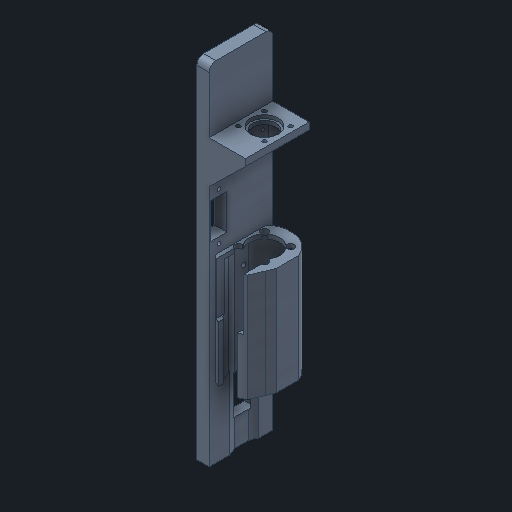
# Autodesk Inventor part: OT2-Pipette V0.3 - frame
Saved by Autodesk Inventor 2026 (Build 300175000, 175)
## iProperties
Created: 2026-11-01
Part Number: OT2-Pipette V0.3 - frame
Material: Generisch
Description: printed frame: mount wall with 3 M3 inserts, sleeve + ledge, header window, motor shelf (PETG/ASA)
Document SubType Name: Modeling
Designer: benir
Density: 1 g/cm^3
Appearance: Light Steel Blue
Author: benir
Autodesk Inventor part; units mm, degrees
ref_plane "WP mount face" through (-9.5, 0, 0) normal (1, 0, 0) x (0, 1, 0)
ref_plane "WP pipette x" through (8.2, 0, 0) normal (1, 0, 0) x (0, 1, 0)
ref_plane "WP pipette z" through (0, 0, -3.46) normal (0, 0, 1) x (1, 0, 0)
ref_plane "WP motor seat" through (0, 119, 0) normal (0, 1, 0) x (-1, 0, 0)
ref_plane "y=ins_top_y" through (0, 46, 0) normal (0, 1, 0) x (-1, 0, 0)
ref_plane "z=ins_z" through (0, 0, 13.25) normal (0, 0, 1) x (1, 0, 0)
ref_plane "z=-ins_z" through (0, 0, -13.25) normal (0, 0, 1) x (1, 0, 0)
ref_plane "y=ins_bot_y" through (0, -43, 0) normal (0, 1, 0) x (-1, 0, 0)
sketch "mount wall" plane through (-9.5, 0, 0) normal (1, 0, 0) x (0, 1, 0)
  line L0 (-49, -18.75) -> (156.35, -18.75)
  line L1 (156.35, -18.75) -> (156.35, 18.75)
  line L2 (156.35, 18.75) -> (-49, 18.75)
  line L3 (-49, 18.75) -> (-49, -18.75)
  line L4 (0, -26.25) -> (0, 26.25) projected
  line L5 (-90.07, 0) -> (197.42, 0) projected
  point P0 (0, 0)
  dimension "d10" = 205.35
  dimension "d11" = 37.5
  dimension "d12" = 49
  dimension "d13" = 18.75
  constraints: 8 end point, 2 parallel, 1 horizontal, 1 perpendicular
  measures "d10" distance of L0.start L0.end
  measures "d11" distance of L2.end L0.start
  measures "d12" horizontal distance of point (0, 0) L2.end
  measures "d13" vertical distance of point (0, 0) L0.start
extrude "Extrusion2" add sketch "mount wall" along normal blind 7.3
fillet "wall top edges" radius 4 2 edges at (-5.85, 156.35, 18.75) (-5.85, 156.35, -18.75)
ref_plane "y=sleeve_y0" through (0, -6, 0) normal (0, 1, 0) x (-1, 0, 0)
sketch "sleeve outline" plane through (0, -6, 0) normal (0, 1, 0) x (-1, 0, 0)
  arc A0 (-20.2, -6.2935) -> (3.8, -6.2935) centre (-8.2, -3.46) ccw construction
  arc A1 (-1.2, 13.79) -> (-15.2, 13.79) centre (-8.2, 2.54) ccw construction
  line L0 (3.8, -6.2935) -> (3.8, 1.71) construction
  line L1 (3.8, 1.71) -> (1.58, 7.29) construction
  line L2 (1.58, 7.29) -> (-1.2, 13.79) construction
  line L3 (-15.2, 13.79) -> (-17.98, 7.29) construction
  line L4 (-17.98, 7.29) -> (-20.2, 1.71) construction
  line L5 (-20.2, 1.71) -> (-20.2, -6.2935) construction
  arc A2 (-23.5, -6.6548) -> (7.1, -6.6548) centre (-8.2, -3.46) ccw
  line L6 (7.1, -6.6548) -> (7.1, 2.3423)
  line L7 (7.1, 2.3423) -> (4.6307, 8.549)
  line L8 (4.6307, 8.549) -> (1.4503, 15.9853)
  arc A3 (1.4503, 15.9853) -> (-17.8503, 15.9853) centre (-8.2, 2.54) ccw
  line L9 (-17.8503, 15.9853) -> (-21.0307, 8.549)
  line L10 (-21.0307, 8.549) -> (-23.5, 2.3423)
  line L11 (-23.5, 2.3423) -> (-23.5, -6.6548)
  point P0 (0, 0)
  dimension "lever_drop" = 1.5
  dimension "d18" = 3.46
  dimension "d19" = 8.2
  dimension "d20" = 2.54
  dimension "d21" = 8.2
  dimension "d22" = 6.2935
  dimension "d23" = 20.2
  dimension "d24" = 3.8
  dimension "d25" = 13.79
  dimension "d26" = 15.2
  dimension "d27" = 1.2
  dimension "d28" = 1.71
  dimension "d29" = 3.8
  dimension "d30" = 7.29
  dimension "d31" = 1.58
  dimension "d32" = 7.29
  dimension "d33" = 17.98
  dimension "d34" = 1.71
  dimension "d35" = 20.2
  dimension "d36" = 3.3
  constraints: 24 end point, 8 point on circle, 4 centre point, 7 other
  measures "d18" vertical distance of point (0, 0) A0.centre
  measures "d19" horizontal distance of point (0, 0) A0.centre
  measures "d20" vertical distance of point (0, 0) A1.centre
  measures "d21" horizontal distance of point (0, 0) A1.centre
  measures "d22" vertical distance of point (0, 0) L5.end
  measures "d23" horizontal distance of point (0, 0) L5.end
  measures "d24" horizontal distance of point (0, 0) L0.start
  measures "d25" vertical distance of point (0, 0) L3.start
  measures "d26" horizontal distance of point (0, 0) L3.start
  measures "d27" horizontal distance of point (0, 0) L2.end
  measures "d28" vertical distance of point (0, 0) L0.end
  measures "d29" horizontal distance of point (0, 0) L0.end
  measures "d30" vertical distance of point (0, 0) L1.end
  measures "d31" horizontal distance of point (0, 0) L1.end
  measures "d32" vertical distance of point (0, 0) L3.end
  measures "d33" horizontal distance of point (0, 0) L3.end
  measures "d34" vertical distance of point (0, 0) L4.end
  measures "d35" horizontal distance of point (0, 0) L4.end
  measures "d36" distance between parallel lines of L6 L0
extrude "sleeve and ledge" add sketch "sleeve outline" along normal blind 63.5
ref_plane "y=mot_front - shelf_t" through (0, 115, 0) normal (0, 1, 0) x (-1, 0, 0)
sketch "motor shelf" plane through (0, 115, 0) normal (0, 1, 0) x (-1, 0, 0)
  line L0 (2.7, -18.75) -> (-19.2, -18.75)
  line L1 (-19.2, -18.75) -> (-19.2, 18.75)
  line L2 (-19.2, 18.75) -> (2.7, 18.75)
  line L3 (2.7, 18.75) -> (2.7, -18.75)
  line L4 (0, -26.726) -> (0, 26.726) projected
  line L5 (16.1, 0) -> (-30.1, 0) projected
  point P0 (0, 0)
  dimension "d40" = 21.9
  dimension "d41" = 37.5
  dimension "d42" = 2.7
  dimension "d43" = 18.75
  constraints: 8 end point, 2 parallel, 1 horizontal, 1 perpendicular
  measures "d40" distance of L0.start L0.end
  measures "d41" distance of L2.end L0.start
  measures "d42" horizontal distance of point (0, 0) L2.end
  measures "d43" vertical distance of point (0, 0) L0.start
extrude "Extrusion4" add sketch "motor shelf" along normal blind 4
ref_plane "z=-env_z" through (0, 0, -18.75) normal (0, 0, 1) x (1, 0, 0)
sketch "gusset -z" plane through (0, 0, -18.75) normal (0, 0, 1) x (1, 0, 0)
  line L0 (-2.7, 115) -> (19.2, 115)
  line L1 (19.2, 115) -> (-2.7, 93.6)
  line L2 (-2.7, 93.6) -> (-2.7, 115)
  point P0 (0, 0)
  dimension "d47" = 115
  dimension "d48" = 2.7
  dimension "d49" = 115
  dimension "d50" = 19.2
  dimension "d51" = 93.6
  dimension "d52" = 2.7
  constraints: 6 end point
  measures "d47" vertical distance of point (0, 0) L0.start
  measures "d48" horizontal distance of point (0, 0) L0.start
  measures "d49" vertical distance of point (0, 0) L0.end
  measures "d50" horizontal distance of point (0, 0) L0.end
  measures "d51" vertical distance of point (0, 0) L1.end
  measures "d52" horizontal distance of point (0, 0) L1.end
extrude "Extrusion5" add sketch "gusset -z" along normal blind 2.5
ref_plane "z=env_z - gusset_t" through (0, 0, 16.25) normal (0, 0, 1) x (1, 0, 0)
sketch "gusset +z" plane through (0, 0, 16.25) normal (0, 0, 1) x (1, 0, 0)
  line L0 (-2.7, 115) -> (19.2, 115)
  line L1 (19.2, 115) -> (-2.7, 93.6)
  line L2 (-2.7, 93.6) -> (-2.7, 115)
  point P0 (0, 0)
  dimension "d56" = 115
  dimension "d57" = 2.7
  dimension "d58" = 115
  dimension "d59" = 19.2
  dimension "d60" = 93.6
  dimension "d61" = 2.7
  constraints: 6 end point
  measures "d56" vertical distance of point (0, 0) L0.start
  measures "d57" horizontal distance of point (0, 0) L0.start
  measures "d58" vertical distance of point (0, 0) L0.end
  measures "d59" horizontal distance of point (0, 0) L0.end
  measures "d60" vertical distance of point (0, 0) L1.end
  measures "d61" horizontal distance of point (0, 0) L1.end
extrude "Extrusion6" add sketch "gusset +z" along normal blind 2.5
ref_plane "y=body_bottom - body_cut_below" through (0, -96, 0) normal (0, 1, 0) x (-1, 0, 0)
sketch "body clearance outline" plane through (0, -96, 0) normal (0, 1, 0) x (-1, 0, 0)
  arc A0 (-20.2, -6.2935) -> (3.8, -6.2935) centre (-8.2, -3.46) ccw construction
  arc A1 (-1.2, 13.79) -> (-15.2, 13.79) centre (-8.2, 2.54) ccw construction
  line L0 (3.8, -6.2935) -> (3.8, 1.71) construction
  line L1 (3.8, 1.71) -> (1.58, 7.29) construction
  line L2 (1.58, 7.29) -> (-1.2, 13.79) construction
  line L3 (-15.2, 13.79) -> (-17.98, 7.29) construction
  line L4 (-17.98, 7.29) -> (-20.2, 1.71) construction
  line L5 (-20.2, 1.71) -> (-20.2, -6.2935) construction
  arc A2 (-20.5, -6.3283) -> (4.1, -6.3283) centre (-8.2, -3.46) ccw
  line L6 (4.1, -6.3283) -> (4.1, 1.7675)
  line L7 (4.1, 1.7675) -> (1.8573, 7.4045)
  line L8 (1.8573, 7.4045) -> (-0.9611, 13.9943)
  arc A3 (-0.9611, 13.9943) -> (-15.4389, 13.9943) centre (-8.2, 2.54) ccw
  line L9 (-15.4389, 13.9943) -> (-18.2573, 7.4045)
  line L10 (-18.2573, 7.4045) -> (-20.5, 1.7675)
  line L11 (-20.5, 1.7675) -> (-20.5, -6.3283)
  point P0 (0, 0)
  dimension "d65" = 3.46
  dimension "d66" = 8.2
  dimension "d67" = 2.54
  dimension "d68" = 8.2
  dimension "d69" = 6.2935
  dimension "d70" = 20.2
  dimension "d71" = 3.8
  dimension "d72" = 13.79
  dimension "d73" = 15.2
  dimension "d74" = 1.2
  dimension "d75" = 1.71
  dimension "d76" = 3.8
  dimension "d77" = 7.29
  dimension "d78" = 1.58
  dimension "d79" = 7.29
  dimension "d80" = 17.98
  dimension "d81" = 1.71
  dimension "d82" = 20.2
  dimension "d83" = 0.3
  constraints: 24 end point, 8 point on circle, 4 centre point, 7 other
  measures "d65" vertical distance of point (0, 0) A0.centre
  measures "d66" horizontal distance of point (0, 0) A0.centre
  measures "d67" vertical distance of point (0, 0) A1.centre
  measures "d68" horizontal distance of point (0, 0) A1.centre
  measures "d69" vertical distance of point (0, 0) L5.end
  measures "d70" horizontal distance of point (0, 0) L5.end
  measures "d71" horizontal distance of point (0, 0) L0.start
  measures "d72" vertical distance of point (0, 0) L3.start
  measures "d73" horizontal distance of point (0, 0) L3.start
  measures "d74" horizontal distance of point (0, 0) L2.end
  measures "d75" vertical distance of point (0, 0) L0.end
  measures "d76" horizontal distance of point (0, 0) L0.end
  measures "d77" vertical distance of point (0, 0) L1.end
  measures "d78" horizontal distance of point (0, 0) L1.end
  measures "d79" vertical distance of point (0, 0) L3.end
  measures "d80" horizontal distance of point (0, 0) L3.end
  measures "d81" vertical distance of point (0, 0) L4.end
  measures "d82" horizontal distance of point (0, 0) L4.end
  measures "d83" distance between parallel lines of L6 L0
extrude "body clearance" cut sketch "body clearance outline" along normal blind 151
ref_plane "y=body_top - cut_over" through (0, 54, 0) normal (0, 1, 0) x (-1, 0, 0)
sketch "knob hole" plane through (0, 54, 0) normal (0, 1, 0) x (-1, 0, 0)
  circle A0 centre (-8.2, -3.46) radius 9.1
  point P0 (0, 0)
  dimension "d87" = 3.46
  dimension "d88" = 8.2
  dimension "d89" = 18.2
  constraints: 1 centre point
  measures "d87" vertical distance of point (0, 0) A0.centre
  measures "d88" horizontal distance of point (0, 0) A0.centre
  measures "d89" diameter of A0
extrude "Extrusion8" cut sketch "knob hole" along normal blind 4.5
ref_plane "y=sleeve_y0 - cut_over" through (0, -7, 0) normal (0, 1, 0) x (-1, 0, 0)
sketch "ejector slot" plane through (0, -7, 0) normal (0, 1, 0) x (-1, 0, 0)
  line L0 (-2.6, 8.34) -> (-13.8, 8.34)
  line L1 (-13.8, 8.34) -> (-13.8, 19.75)
  line L2 (-13.8, 19.75) -> (-2.6, 19.75)
  line L3 (-2.6, 19.75) -> (-2.6, 8.34)
  line L4 (0, -26.858) -> (0, 27.518) projected
  line L5 (16.1, 0) -> (-30.1, 0) projected
  point P0 (0, 0)
  dimension "d93" = 11.2
  dimension "d94" = 11.41
  dimension "d95" = 2.6
  dimension "d96" = 8.34
  constraints: 8 end point, 2 parallel, 1 horizontal, 1 perpendicular
  measures "d93" distance of L0.start L0.end
  measures "d94" distance of L2.end L0.start
  measures "d95" horizontal distance of point (0, 0) L2.end
  measures "d96" vertical distance of point (0, 0) L0.start
extrude "ejector button slot" cut sketch "ejector slot" along normal blind 62
ref_plane "y=body_top - eject_win_h" through (0, 27, 0) normal (0, 1, 0) x (-1, 0, 0)
sketch "eject window" plane through (0, 27, 0) normal (0, 1, 0) x (-1, 0, 0)
  line L0 (-0.2, 5.04) -> (-16.2, 5.04)
  line L1 (-16.2, 5.04) -> (-16.2, 19.75)
  line L2 (-16.2, 19.75) -> (-0.2, 19.75)
  line L3 (-0.2, 19.75) -> (-0.2, 5.04)
  line L4 (0, -26.858) -> (0, 27.518) projected
  line L5 (16.1, 0) -> (-30.1, 0) projected
  point P0 (0, 0)
  dimension "d100" = 16
  dimension "d101" = 14.71
  dimension "d102" = 0.2
  dimension "d103" = 5.04
  constraints: 8 end point, 2 parallel, 1 horizontal, 1 perpendicular
  measures "d100" distance of L0.start L0.end
  measures "d101" distance of L2.end L0.start
  measures "d102" horizontal distance of point (0, 0) L2.end
  measures "d103" vertical distance of point (0, 0) L0.start
extrude "Extrusion10" cut sketch "eject window" along normal blind 31.5
sketch "ledge relief" plane through (0, 54, 0) normal (0, 1, 0) x (-1, 0, 0)
  line L0 (-0.5, -3.46) -> (-15.9, -3.46)
  line L1 (-15.9, -3.46) -> (-15.9, 5.04)
  line L2 (-15.9, 5.04) -> (-0.5, 5.04)
  line L3 (-0.5, 5.04) -> (-0.5, -3.46)
  line L4 (0, -26.658) -> (0, 26.318) projected
  line L5 (16.1, 0) -> (-30.1, 0) projected
  point P0 (0, 0)
  dimension "d106" = 15.4
  dimension "d107" = 8.5
  dimension "d108" = 0.5
  dimension "d109" = 3.46
  constraints: 8 end point, 2 parallel, 1 horizontal, 1 perpendicular
  measures "d106" distance of L0.start L0.end
  measures "d107" distance of L2.end L0.start
  measures "d108" horizontal distance of point (0, 0) L2.end
  measures "d109" vertical distance of point (0, 0) L0.start
extrude "Extrusion11" cut sketch "ledge relief" along normal blind 4.5
ref_plane "y=body_bottom + disp_y0" through (0, -33, 0) normal (0, 1, 0) x (-1, 0, 0)
sketch "volume window" plane through (0, -33, 0) normal (0, 1, 0) x (-1, 0, 0)
  line L0 (10.5, -9.46) -> (3.8, -9.46)
  line L1 (3.8, -9.46) -> (3.8, 2.54)
  line L2 (3.8, 2.54) -> (10.5, 2.54)
  line L3 (10.5, 2.54) -> (10.5, -9.46)
  line L4 (0, -26.658) -> (0, 26.318) projected
  line L5 (17.3, 0) -> (-30.3, 0) projected
  point P0 (0, 0)
  dimension "d113" = 6.7
  dimension "d114" = 12
  dimension "d115" = 10.5
  dimension "d116" = 9.46
  constraints: 8 end point, 2 parallel, 1 horizontal, 1 perpendicular
  measures "d113" distance of L0.start L0.end
  measures "d114" distance of L2.end L0.start
  measures "d115" horizontal distance of point (0, 0) L2.end
  measures "d116" vertical distance of point (0, 0) L0.start
extrude "Extrusion12" cut sketch "volume window" along normal blind 23
ref_plane "x=mount_x - cut_over" through (-10.5, 0, 0) normal (1, 0, 0) x (0, 1, 0)
sketch "insert holes" plane through (-10.5, 0, 0) normal (1, 0, 0) x (0, 1, 0)
  circle A0 centre (46, 13.25) radius 2.05
  circle A1 centre (46, -13.25) radius 2.05
  circle A2 centre (-43, -13.25) radius 2.05
  point P0 (0, 0)
  dimension "d120" = 13.25
  dimension "d121" = 46
  dimension "d122" = 4.1
  dimension "d123" = 13.25
  dimension "d124" = 46
  dimension "d125" = 4.1
  dimension "d126" = 13.25
  dimension "d127" = 43
  dimension "d128" = 4.1
  constraints: 3 centre point
  measures "d120" vertical distance of point (0, 0) A0.centre
  measures "d121" horizontal distance of point (0, 0) A0.centre
  measures "d122" diameter of A0
  measures "d123" vertical distance of point (0, 0) A1.centre
  measures "d124" horizontal distance of point (0, 0) A1.centre
  measures "d125" diameter of A1
  measures "d126" vertical distance of point (0, 0) A2.centre
  measures "d127" horizontal distance of point (0, 0) A2.centre
  measures "d128" diameter of A2
extrude "Extrusion13" cut sketch "insert holes" along normal blind 7.7
sketch "insert recesses" plane through (-10.5, 0, 0) normal (1, 0, 0) x (0, 1, 0)
  circle A0 centre (46, 13.25) radius 3
  circle A1 centre (46, -13.25) radius 3
  circle A2 centre (-43, -13.25) radius 3
  point P0 (0, 0)
  dimension "d131" = 13.25
  dimension "d132" = 46
  dimension "d133" = 6
  dimension "d134" = 13.25
  dimension "d135" = 46
  dimension "d136" = 6
  dimension "d137" = 13.25
  dimension "d138" = 43
  dimension "d139" = 6
  constraints: 3 centre point
  measures "d131" vertical distance of point (0, 0) A0.centre
  measures "d132" horizontal distance of point (0, 0) A0.centre
  measures "d133" diameter of A0
  measures "d134" vertical distance of point (0, 0) A1.centre
  measures "d135" horizontal distance of point (0, 0) A1.centre
  measures "d136" diameter of A1
  measures "d137" vertical distance of point (0, 0) A2.centre
  measures "d138" horizontal distance of point (0, 0) A2.centre
  measures "d139" diameter of A2
extrude "Extrusion14" cut sketch "insert recesses" along normal blind 1.3
sketch "grub screw holes" plane through (-10.5, 0, 0) normal (1, 0, 0) x (0, 1, 0)
  circle A0 centre (4, -3.46) radius 1.25
  circle A1 centre (42, -3.46) radius 1.25
  point P0 (0, 0)
  dimension "d142" = 3.46
  dimension "d143" = 4
  dimension "d144" = 2.5
  dimension "d145" = 3.46
  dimension "d146" = 42
  dimension "d147" = 2.5
  constraints: 2 centre point
  measures "d142" vertical distance of point (0, 0) A0.centre
  measures "d143" horizontal distance of point (0, 0) A0.centre
  measures "d144" diameter of A0
  measures "d145" vertical distance of point (0, 0) A1.centre
  measures "d146" horizontal distance of point (0, 0) A1.centre
  measures "d147" diameter of A1
extrude "M3 grub screw holes" cut sketch "grub screw holes" along normal blind 7.7
ref_plane "y=mot_front - mot_pilot_h - pilot_clr" through (0, 117.1, 0) normal (0, 1, 0) x (-1, 0, 0)
sketch "motor pilot recess" plane through (0, 117.1, 0) normal (0, 1, 0) x (-1, 0, 0)
  circle A0 centre (-8.2, -3.46) radius 8.2
  point P0 (0, 0)
  dimension "d151" = 3.46
  dimension "d152" = 8.2
  dimension "d153" = 16.4
  constraints: 1 centre point
  measures "d151" vertical distance of point (0, 0) A0.centre
  measures "d152" horizontal distance of point (0, 0) A0.centre
  measures "d153" diameter of A0
extrude "Extrusion16" cut sketch "motor pilot recess" along normal blind 2.9
ref_plane "y=mot_front - shelf_t - cut_over" through (0, 114, 0) normal (0, 1, 0) x (-1, 0, 0)
sketch "motor boss hole" plane through (0, 114, 0) normal (0, 1, 0) x (-1, 0, 0)
  circle A0 centre (-8.2, -3.46) radius 6.9
  point P0 (0, 0)
  dimension "d157" = 3.46
  dimension "d158" = 8.2
  dimension "d159" = 13.8
  constraints: 1 centre point
  measures "d157" vertical distance of point (0, 0) A0.centre
  measures "d158" horizontal distance of point (0, 0) A0.centre
  measures "d159" diameter of A0
extrude "Extrusion17" cut sketch "motor boss hole" along normal blind 6
sketch "motor screw holes" plane through (0, 114, 0) normal (0, 1, 0) x (-1, 0, 0)
  circle A0 centre (-0.5, -11.16) radius 1.2
  circle A1 centre (-0.5, 4.24) radius 1.2
  circle A2 centre (-15.9, -11.16) radius 1.2
  circle A3 centre (-15.9, 4.24) radius 1.2
  point P0 (0, 0)
  dimension "d162" = 11.16
  dimension "d163" = 0.5
  dimension "d164" = 2.4
  dimension "d165" = 4.24
  dimension "d166" = 0.5
  dimension "d167" = 2.4
  dimension "d168" = 11.16
  dimension "d169" = 15.9
  dimension "d170" = 2.4
  dimension "d171" = 4.24
  dimension "d172" = 15.9
  dimension "d173" = 2.4
  constraints: 4 centre point
  measures "d162" vertical distance of point (0, 0) A0.centre
  measures "d163" horizontal distance of point (0, 0) A0.centre
  measures "d164" diameter of A0
  measures "d165" vertical distance of point (0, 0) A1.centre
  measures "d166" horizontal distance of point (0, 0) A1.centre
  measures "d167" diameter of A1
  measures "d168" vertical distance of point (0, 0) A2.centre
  measures "d169" horizontal distance of point (0, 0) A2.centre
  measures "d170" diameter of A2
  measures "d171" vertical distance of point (0, 0) A3.centre
  measures "d172" horizontal distance of point (0, 0) A3.centre
  measures "d173" diameter of A3
extrude "4 x M2 motor screw holes" cut sketch "motor screw holes" along normal blind 6
sketch "screwdriver channels" plane through (0, 54, 0) normal (0, 1, 0) x (-1, 0, 0)
  circle A0 centre (-0.5, -11.16) radius 2.2
  circle A1 centre (-0.5, 4.24) radius 2.2
  circle A2 centre (-15.9, -11.16) radius 2.2
  circle A3 centre (-15.9, 4.24) radius 2.2
  point P0 (0, 0)
  dimension "d176" = 11.16
  dimension "d177" = 0.5
  dimension "d178" = 4.4
  dimension "d179" = 4.24
  dimension "d180" = 0.5
  dimension "d181" = 4.4
  dimension "d182" = 11.16
  dimension "d183" = 15.9
  dimension "d184" = 4.4
  dimension "d185" = 4.24
  dimension "d186" = 15.9
  dimension "d187" = 4.4
  constraints: 4 centre point
  measures "d176" vertical distance of point (0, 0) A0.centre
  measures "d177" horizontal distance of point (0, 0) A0.centre
  measures "d178" diameter of A0
  measures "d179" vertical distance of point (0, 0) A1.centre
  measures "d180" horizontal distance of point (0, 0) A1.centre
  measures "d181" diameter of A1
  measures "d182" vertical distance of point (0, 0) A2.centre
  measures "d183" horizontal distance of point (0, 0) A2.centre
  measures "d184" diameter of A2
  measures "d185" vertical distance of point (0, 0) A3.centre
  measures "d186" horizontal distance of point (0, 0) A3.centre
  measures "d187" diameter of A3
extrude "Extrusion19" cut sketch "screwdriver channels" along normal blind 62
sketch "header window" plane through (-10.5, 0, 0) normal (1, 0, 0) x (0, 1, 0)
  line L0 (65.55, 8.25) -> (86.45, 8.25)
  line L1 (86.45, 8.25) -> (86.45, 17.75)
  line L2 (86.45, 17.75) -> (65.55, 17.75)
  line L3 (65.55, 17.75) -> (65.55, 8.25)
  line L4 (0, -26.658) -> (0, 26.318) projected
  line L5 (-90.07, 0) -> (197.42, 0) projected
  point P0 (0, 0)
  dimension "d190" = 20.9
  dimension "d191" = 9.5
  dimension "d192" = 65.55
  dimension "d193" = 8.25
  constraints: 8 end point, 2 parallel, 1 horizontal, 1 perpendicular
  measures "d190" distance of L0.start L0.end
  measures "d191" distance of L2.end L0.start
  measures "d192" horizontal distance of point (0, 0) L2.end
  measures "d193" vertical distance of point (0, 0) L0.start
extrude "2x5 header window" cut sketch "header window" along normal blind 9.3
ref_plane "x=wall_x1 + cut_over" through (-1.2, 0, 0) normal (1, 0, 0) x (0, 1, 0)
sketch "board screw holes" plane through (-1.2, 0, 0) normal (1, 0, 0) x (0, 1, 0)
  circle A0 centre (62.05, 13) radius 1.1
  circle A1 centre (89.95, 13) radius 1.1
  point P0 (0, 0)
  dimension "d197" = 13
  dimension "d198" = 62.05
  dimension "d199" = 2.2
  dimension "d200" = 13
  dimension "d201" = 89.95
  dimension "d202" = 2.2
  constraints: 2 centre point
  measures "d197" vertical distance of point (0, 0) A0.centre
  measures "d198" horizontal distance of point (0, 0) A0.centre
  measures "d199" diameter of A0
  measures "d200" vertical distance of point (0, 0) A1.centre
  measures "d201" horizontal distance of point (0, 0) A1.centre
  measures "d202" diameter of A1
extrude "identity board screw holes" cut sketch "board screw holes" against normal blind 7
sketch "switch screw holes" plane through (-1.2, 0, 0) normal (1, 0, 0) x (0, 1, 0)
  circle A0 centre (107.3, -12.85) radius 0.9
  circle A1 centre (107.3, -6.35) radius 0.9
  point P0 (0, 0)
  dimension "d205" = 12.85
  dimension "d206" = 107.3
  dimension "d207" = 1.8
  dimension "d208" = 6.35
  dimension "d209" = 107.3
  dimension "d210" = 1.8
  constraints: 2 centre point
  measures "d205" vertical distance of point (0, 0) A0.centre
  measures "d206" horizontal distance of point (0, 0) A0.centre
  measures "d207" diameter of A0
  measures "d208" vertical distance of point (0, 0) A1.centre
  measures "d209" horizontal distance of point (0, 0) A1.centre
  measures "d210" diameter of A1
extrude "Extrusion22" cut sketch "switch screw holes" against normal blind 7
ref_plane "y=plate_y0 - cut_over" through (0, -50, 0) normal (0, 1, 0) x (-1, 0, 0)
sketch "GEN2 outline trim" plane through (0, -50, 0) normal (0, 1, 0) x (-1, 0, 0)
  line L0 (59.5, -68.75) -> (-72.84, -68.75)
  line L1 (-72.84, -68.75) -> (-72.84, 68.75)
  line L2 (-72.84, 68.75) -> (59.5, 68.75)
  line L3 (59.5, 68.75) -> (59.5, -68.75)
  line L4 (0, -96.25) -> (0, 96.25) projected
  line L5 (85.968, 0) -> (-99.308, 0) projected
  line L6 (9.5, -18.75) -> (-22.84, -18.75)
  line L7 (-22.84, -18.75) -> (-22.84, 18.75)
  line L8 (-22.84, 18.75) -> (9.5, 18.75)
  line L9 (9.5, 18.75) -> (9.5, -18.75)
  point P0 (0, 0)
  dimension "d214" = 132.34
  dimension "d215" = 137.5
  dimension "d216" = 59.5
  dimension "d217" = 68.75
  dimension "d218" = 32.34
  dimension "d219" = 37.5
  dimension "d220" = 9.5
  dimension "d221" = 18.75
  constraints: 16 end point, 4 parallel, 2 horizontal, 2 perpendicular
  measures "d214" distance of L0.start L0.end
  measures "d215" distance of L2.end L0.start
  measures "d216" horizontal distance of point (0, 0) L2.end
  measures "d217" vertical distance of point (0, 0) L0.start
  measures "d218" distance of L6.start L6.end
  measures "d219" distance of L8.end L6.start
  measures "d220" horizontal distance of point (0, 0) L8.end
  measures "d221" vertical distance of point (0, 0) L6.start
extrude "trim to the GEN2 outline" cut sketch "GEN2 outline trim" along normal through all both and the other way through all contours L0 L4 L6 L9 L5 L3 | L0 L1 L5 L7 L6 L4 | L5 L9 L8 L4 L2 L3 | L1 L2 L4 L8 L7 L5
equation "\"d10\" = mot_rear - plate_y0"
equation "\"d11\" = 2 * env_z"
equation "\"d12\" = -plate_y0"
equation "\"d13\" = env_z"
equation "\"d14\" = wall_x1 - mount_x"
equation "\"d16\" = wall_fillet"
equation "\"d18\" = -pip_z"
equation "\"d19\" = pip_x"
equation "\"d20\" = pip_z + nose_c"
equation "\"d21\" = pip_x"
equation "\"d23\" = pip_x + body_hw"
equation "\"d24\" = body_hw - pip_x"
equation "\"d26\" = pip_x + nose_hw"
equation "\"d27\" = pip_x - nose_hw"
equation "\"d28\" = pip_z + body_flat_d"
equation "\"d29\" = body_hw - pip_x"
equation "\"d30\" = pip_z + body_ch_d"
equation "\"d31\" = body_ch_w - pip_x"
equation "\"d32\" = pip_z + body_ch_d"
equation "\"d33\" = pip_x + body_ch_w"
equation "\"d34\" = pip_z + body_flat_d"
equation "\"d35\" = pip_x + body_hw"
equation "\"d36\" = wall_out"
equation "\"d37\" = ledge_t + body_top - sleeve_y0"
equation "\"d40\" = shelf_x1 + shelf_back - wall_x1"
equation "\"d41\" = 2 * env_z"
equation "\"d42\" = shelf_back - wall_x1"
equation "\"d43\" = env_z"
equation "\"d44\" = shelf_t"
equation "\"d47\" = mot_front - shelf_t"
equation "\"d48\" = shelf_back - wall_x1"
equation "\"d49\" = mot_front - shelf_t"
equation "\"d50\" = shelf_x1"
equation "\"d51\" = -shelf_t + mot_front - gusset_h"
equation "\"d52\" = shelf_back - wall_x1"
equation "\"d53\" = gusset_t"
equation "\"d56\" = mot_front - shelf_t"
equation "\"d57\" = shelf_back - wall_x1"
equation "\"d58\" = mot_front - shelf_t"
equation "\"d59\" = shelf_x1"
equation "\"d60\" = -shelf_t + mot_front - gusset_h"
equation "\"d61\" = shelf_back - wall_x1"
equation "\"d62\" = gusset_t"
equation "\"d65\" = -pip_z"
equation "\"d66\" = pip_x"
equation "\"d67\" = pip_z + nose_c"
equation "\"d68\" = pip_x"
equation "\"d70\" = pip_x + body_hw"
equation "\"d71\" = body_hw - pip_x"
equation "\"d73\" = pip_x + nose_hw"
equation "\"d74\" = pip_x - nose_hw"
equation "\"d75\" = pip_z + body_flat_d"
equation "\"d76\" = body_hw - pip_x"
equation "\"d77\" = pip_z + body_ch_d"
equation "\"d78\" = body_ch_w - pip_x"
equation "\"d79\" = pip_z + body_ch_d"
equation "\"d80\" = pip_x + body_ch_w"
equation "\"d81\" = pip_z + body_flat_d"
equation "\"d82\" = pip_x + body_hw"
equation "\"d83\" = clr"
equation "\"d84\" = body_len + body_cut_below"
equation "\"d87\" = -pip_z"
equation "\"d88\" = pip_x"
equation "\"d89\" = knob_hole_d"
equation "\"d90\" = ledge_t + 2 * cut_over"
equation "\"d93\" = 2 * ej_slot_clr + 0 * pip_x + 2 * ej_hw"
equation "\"d94\" = cut_over + env_z + ej_slot_z - pip_z - ej_d0"
equation "\"d95\" = -ej_hw + pip_x - ej_slot_clr"
equation "\"d96\" = ej_d0 + pip_z - ej_slot_z"
equation "\"d97\" = -sleeve_y0 + body_top + cut_over"
equation "\"d100\" = 2 * eject_win_hw + 0 * pip_x"
equation "\"d101\" = cut_over + env_z - eject_win_d - pip_z"
equation "\"d102\" = pip_x - eject_win_hw"
equation "\"d103\" = pip_z + eject_win_d"
equation "\"d104\" = ledge_t + eject_win_h + cut_over"
equation "\"d106\" = mot_holes + 0 * pip_x"
equation "\"d107\" = eject_win_d + 0 * pip_z"
equation "\"d108\" = pip_x - 0.5 * mot_holes"
equation "\"d109\" = -pip_z"
equation "\"d110\" = ledge_t + 2 * cut_over"
equation "\"d113\" = -body_hw + pip_x + cut_over - mount_x"
equation "\"d114\" = 2 * disp_hw + 0 * pip_z"
equation "\"d115\" = cut_over - mount_x"
equation "\"d116\" = disp_hw - pip_z"
equation "\"d117\" = disp_y1 - disp_y0"
equation "\"d120\" = ins_z"
equation "\"d121\" = ins_top_y"
equation "\"d122\" = insert_d"
equation "\"d123\" = ins_z"
equation "\"d124\" = ins_top_y"
equation "\"d125\" = insert_d"
equation "\"d126\" = ins_z"
equation "\"d127\" = -ins_bot_y"
equation "\"d128\" = insert_d"
equation "\"d129\" = -mount_x + insert_x_end + cut_over"
equation "\"d131\" = ins_z"
equation "\"d132\" = ins_top_y"
equation "\"d133\" = insert_cb_d"
equation "\"d134\" = ins_z"
equation "\"d135\" = ins_top_y"
equation "\"d136\" = insert_cb_d"
equation "\"d137\" = ins_z"
equation "\"d138\" = -ins_bot_y"
equation "\"d139\" = insert_cb_d"
equation "\"d140\" = insert_cb_h + cut_over"
equation "\"d142\" = -pip_z"
equation "\"d143\" = body_bottom + grub_y1"
equation "\"d144\" = grub_d"
equation "\"d145\" = -pip_z"
equation "\"d146\" = body_bottom + grub_y2"
equation "\"d147\" = grub_d"
equation "\"d148\" = -mount_x - body_hw + pip_x + grub_into + cut_over"
equation "\"d151\" = -pip_z"
equation "\"d152\" = pip_x"
equation "\"d153\" = mot_pilot_d + pilot_clr"
equation "\"d154\" = pilot_clr + mot_pilot_h + cut_over"
equation "\"d157\" = -pip_z"
equation "\"d158\" = pip_x"
equation "\"d159\" = mot_boss_d + boss_clr"
equation "\"d160\" = shelf_t + 2 * cut_over"
equation "\"d162\" = 0.5 * mot_holes - pip_z"
equation "\"d163\" = pip_x - 0.5 * mot_holes"
equation "\"d164\" = m2_clear_d"
equation "\"d165\" = pip_z + 0.5 * mot_holes"
equation "\"d166\" = pip_x - 0.5 * mot_holes"
equation "\"d167\" = m2_clear_d"
equation "\"d168\" = 0.5 * mot_holes - pip_z"
equation "\"d169\" = pip_x + 0.5 * mot_holes"
equation "\"d170\" = m2_clear_d"
equation "\"d171\" = pip_z + 0.5 * mot_holes"
equation "\"d172\" = pip_x + 0.5 * mot_holes"
equation "\"d173\" = m2_clear_d"
equation "\"d174\" = shelf_t + 2 * cut_over"
equation "\"d176\" = 0.5 * mot_holes - pip_z"
equation "\"d177\" = pip_x - 0.5 * mot_holes"
equation "\"d178\" = driver_d"
equation "\"d179\" = pip_z + 0.5 * mot_holes"
equation "\"d180\" = pip_x - 0.5 * mot_holes"
equation "\"d181\" = driver_d"
equation "\"d182\" = 0.5 * mot_holes - pip_z"
equation "\"d183\" = pip_x + 0.5 * mot_holes"
equation "\"d184\" = driver_d"
equation "\"d185\" = pip_z + 0.5 * mot_holes"
equation "\"d186\" = pip_x + 0.5 * mot_holes"
equation "\"d187\" = driver_d"
equation "\"d188\" = -body_top + mot_front - shelf_t + 2 * cut_over"
equation "\"d190\" = hdr_l + 0 * hdr_y"
equation "\"d191\" = hdr_w + 0 * hdr_z"
equation "\"d192\" = hdr_y - 0.5 * hdr_l"
equation "\"d193\" = hdr_z - 0.5 * hdr_w"
equation "\"d194\" = -mount_x + wall_x1 + 2 * cut_over"
equation "\"d197\" = hdr_z"
equation "\"d198\" = -0.5 * hdr_l + hdr_y - pcb_hole_off"
equation "\"d199\" = pcb_hole_d"
equation "\"d200\" = hdr_z"
equation "\"d201\" = 0.5 * hdr_l + hdr_y + pcb_hole_off"
equation "\"d202\" = pcb_hole_d"
equation "\"d203\" = hole_depth + cut_over"
equation "\"d205\" = 0.5 * sw_pitch - 0.5 * sw_l - sw_z0"
equation "\"d206\" = sw_h + sw_y0 - sw_hole_down"
equation "\"d207\" = sw_pilot_d"
equation "\"d208\" = -0.5 * sw_pitch - 0.5 * sw_l - sw_z0"
equation "\"d209\" = sw_h + sw_y0 - sw_hole_down"
equation "\"d210\" = sw_pilot_d"
equation "\"d211\" = hole_depth + cut_over"
equation "\"d218\" = env_x1 - mount_x"
equation "\"d219\" = 2 * env_z"
equation "\"d220\" = -mount_x"
equation "\"d221\" = env_z"
equation "\"mot_rear\" = 156.35"
equation "\"plate_y0\" = -49"
equation "\"env_z\" = 18.75"
equation "\"wall_x1\" = -2.2"
equation "\"mount_x\" = -9.5"
equation "\"wall_fillet\" = 4"
equation "\"wall_out\" = 3.3"
equation "\"ledge_t\" = 2.5"
equation "\"body_top\" = 55"
equation "\"sleeve_y0\" = -6"
equation "\"shelf_x1\" = 19.2"
equation "\"shelf_back\" = 0.5"
equation "\"shelf_t\" = 4"
equation "\"gusset_t\" = 2.5"
equation "\"clr\" = 0.3"
equation "\"body_len\" = 121"
equation "\"body_cut_below\" = 30"
equation "\"knob_hole_d\" = 18.2"
equation "\"cut_over\" = 1"
equation "\"ej_slot_clr\" = 0.6"
equation "\"pip_x\" = 8.2"
equation "\"ej_hw\" = 5"
equation "\"ej_slot_z\" = 0.5"
equation "\"pip_z\" = -3.46"
equation "\"ej_d0\" = 12.3"
equation "\"eject_win_hw\" = 8"
equation "\"eject_win_d\" = 8.5"
equation "\"eject_win_h\" = 28"
equation "\"mot_holes\" = 15.4"
equation "\"body_hw\" = 12"
equation "\"disp_hw\" = 6"
equation "\"disp_y1\" = 56"
equation "\"disp_y0\" = 33"
equation "\"insert_d\" = 4.1"
equation "\"insert_x_end\" = -2.8"
equation "\"insert_cb_d\" = 6"
equation "\"insert_cb_h\" = 0.3"
equation "\"grub_d\" = 2.5"
equation "\"grub_into\" = 1"
equation "\"mot_pilot_d\" = 16"
equation "\"pilot_clr\" = 0.4"
equation "\"mot_pilot_h\" = 1.5"
equation "\"mot_boss_d\" = 13"
equation "\"boss_clr\" = 0.8"
equation "\"m2_clear_d\" = 2.4"
equation "\"driver_d\" = 4.4"
equation "\"mot_front\" = 119"
equation "\"hdr_l\" = 20.9"
equation "\"hdr_y\" = 76"
equation "\"hdr_w\" = 9.5"
equation "\"hdr_z\" = 13"
equation "\"pcb_hole_d\" = 2.2"
equation "\"hole_depth\" = 6"
equation "\"sw_pilot_d\" = 1.8"
equation "\"env_x1\" = 22.84"
equation "\"nose_c\" = 6"
equation "\"nose_hw\" = 7"
equation "\"body_flat_d\" = 5.17"
equation "\"body_ch_d\" = 10.75"
equation "\"body_ch_w\" = 9.78"
equation "\"gusset_h\" = 21.4"
equation "\"ins_z\" = 13.25"
equation "\"ins_top_y\" = 46"
equation "\"ins_bot_y\" = -43"
equation "\"body_bottom\" = -66"
equation "\"grub_y1\" = 70"
equation "\"grub_y2\" = 108"
equation "\"pcb_hole_off\" = 3.5"
equation "\"sw_pitch\" = 6.5"
equation "\"sw_l\" = 12.8"
equation "\"sw_z0\" = -16"
equation "\"sw_h\" = 6.5"
equation "\"sw_y0\" = 103.7"
equation "\"sw_hole_down\" = 2.9"
body "Solid2"
